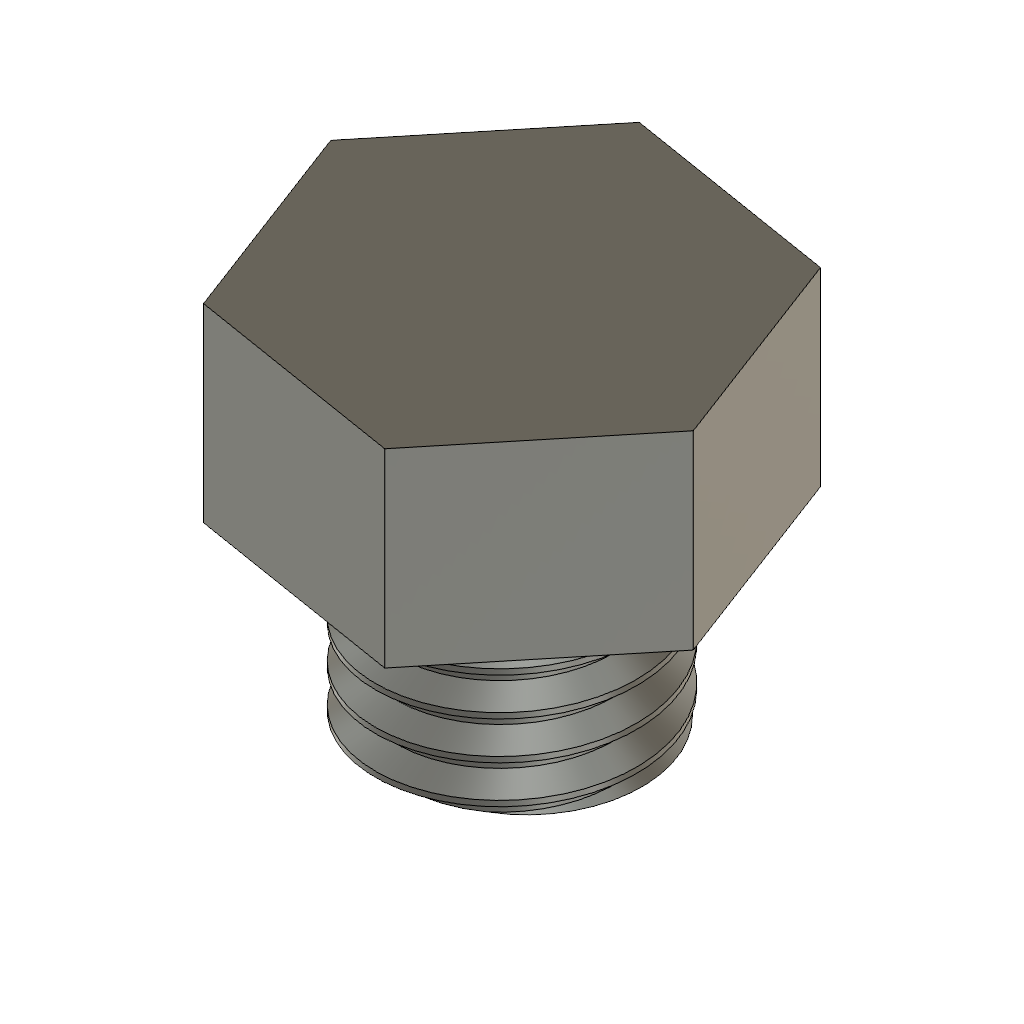
Screw for lens cover (Autodesk Fusion 360 design; units mm, degrees)
Autodesk Fusion 360 part; units mm, degrees
sketch "Sketch1" plane through (0, 0, 0) normal (0, 0, 1) x (1, 0, 0)
  circle A0 centre (0, 0) radius 3.5
  dimension "d1" = 7
  constraint coincident A0.centre origin
  measures "d1" diameter of A0
extrude "Extrude1" add sketch "Sketch1" along normal blind 5
thread "Thread1" "ISO Metric profile 7.0 M7x1 M7x1 6g" major diameter 6.884 minor diameter 5.744 pitch 1 angle 60 modelled right hand crest width 0.1446 on face at (3.4956, -0.1745, 3.3333) crest through (3.442, 0, -0.25)
sketch "Sketch2" plane through (0, 0, 5) normal (0, 0, 1) x (-1, 0, 0)
  line L0 (-3.6512, -4.4724) -> (2.0476, -5.3982)
  line L1 (2.0476, -5.3982) -> (5.6988, -0.9258)
  line L2 (5.6988, -0.9258) -> (3.6512, 4.4724)
  line L3 (3.6512, 4.4724) -> (-2.0476, 5.3982)
  line L4 (-2.0476, 5.3982) -> (-5.6988, 0.9258)
  line L5 (-5.6988, 0.9258) -> (-3.6512, -4.4724)
  spline S0 degree 3 poles (1.5108, -3.0927) (1.8895, -2.8686) (2.2216, -2.5737) (2.7435, -1.8828) (2.9326, -1.4966) (3.146, -0.6861) (3.1733, -0.2711) (3.0667, 0.5321) (2.9389, 0.9131) (2.6109, 1.4838) (2.4525, 1.6916) (2.0894, 2.0556) (1.8874, 2.2114) (1.6675, 2.3384) knots 0 0 0 0 0.132024 0.132024 0.259957 0.259957 0.383795 0.383795 0.503539 0.503539 0.581826 0.581826 0.658261 0.658261 0.658261 0.658261
  arc A0 (1.6675, 2.3384) -> (-1.6675, 2.3384) centre (0, 0) ccw
  spline S1 degree 3 poles (-1.6675, 2.3384) (-1.9957, 2.1488) (-2.2829, 1.8959) (-2.755, 1.2848) (-2.9311, 0.9293) (-3.1433, 0.1579) (-3.1723, -0.2519) (-3.0724, -1.0738) (-2.9393, -1.4773) (-2.5912, -2.0994) (-2.4153, -2.334) (-2.0032, -2.7562) (-1.7674, -2.9409) (-1.5108, -3.0927) knots 0 0 0 0 0.1137 0.1137 0.231484 0.231484 0.35335 0.35335 0.479296 0.479296 0.566597 0.566597 0.655752 0.655752 0.655752 0.655752
  arc A1 (-1.5108, -3.0927) -> (1.5108, -3.0927) centre (0, 0) ccw
  dimension "d6" = 5
  measures "d6" distance of A0.centre L5
extrude "Extrude2" add sketch "Sketch2" along normal blind 5 contours L0 L1 L2 L3 L4 L5 | S0 A0 S1 A1
